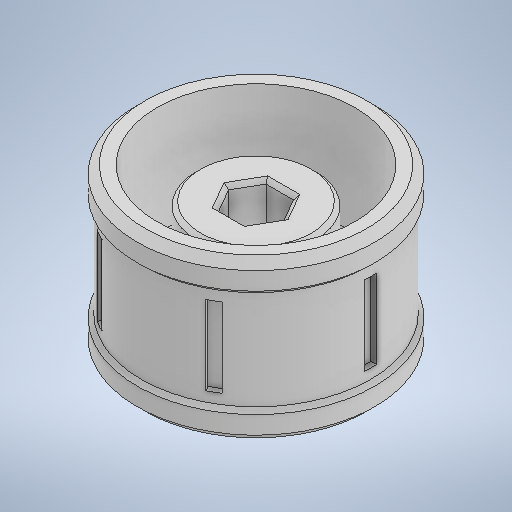
# Autodesk Inventor part: WHEEL RIM
Saved by Autodesk Inventor 2026.3 (Build 303398000, 398)
## iProperties
Created: 2026-10-19
Part Number: WHEEL RIM
Material: Generic
Document SubType Name: Modeling
Designer: Salim
Density: 1 g/cm^3
Appearance: Default
Author: Salim
Autodesk Inventor part; units mm, degrees
ref_plane "YZ Plane" through (0, 0, 0) normal (1, 0, 0) x (0, 1, 0)
ref_plane "XZ Plane" through (0, 0, 0) normal (0, 1, 0) x (-1, 0, 0)
sketch "Sketch1" plane through (0, 0, 0) normal (0, 1, 0) x (-1, 0, 0)
  line L0 (-3.4641, -6) -> (-6.9282, 0)
  line L1 (-6.9282, 0) -> (-3.4641, 6)
  line L2 (-3.4641, 6) -> (3.4641, 6)
  line L3 (3.4641, 6) -> (6.9282, 0)
  line L4 (6.9282, 0) -> (3.4641, -6)
  line L5 (3.4641, -6) -> (-3.4641, -6)
  circle A0 centre (0, 0) radius 40
  circle A1 centre (0, 0) radius 30
  circle A2 centre (0, 0) radius 15
  circle A3 centre (0, 0) radius 25
  dimension "hex" = 12
  dimension "tire" = 80
  dimension "rim" = 60
  dimension "d5" = 30
  dimension "d8" = 50
  constraints: 12 end point, 5 coincident, 4 centre point, 13 other
  measures "hex" distance between parallel lines of L5 L2
  measures "tire" diameter of A0
  measures "rim" diameter of A1
  measures "d5" diameter of A2
  measures "d8" diameter of A3
extrude "Extrusion1" add sketch "Sketch1" along normal blind 40 contours A1
ref_plane "Work Plane1" through (0, 20, 0) normal (0, -1, 0) x (1, 0, 0)
extrude "Extrusion3" add sketch "Sketch1" along normal blind 12 from surface at 20 contours A2
sketch "Sketch2" plane through (0, 20, 0) normal (0, -1, 0) x (1, 0, 0)
  circle A0 centre (0, 0) radius 30 projected
  circle A1 centre (0, 0) radius 15
  dimension "d12" = 30
  constraints: 1 centre point, 1 coincident
  measures "d12" diameter of A1
loft "Loft1" add profiles "Sketch1", "Sketch2" separate body contours L0 L1 L2 L3 L4 L5 | A1 | A2 | A3 / A1
shell "Shell1" thickness 5 removed faces 2 at (-27.8006, 0, -4.3875) at (8.8546, 0, 0.1391) bodies 2
combine bodies "Combine1" operation type add bodies to combine 2 1
fillet "Fillet1" radius 2 1 edges at (25, 6.6667, 0)
sketch "Sketch3" plane through (0, 15, 0) normal (0, -1, 0) x (1, 0, 0)
  circle A0 centre (0, 0) radius 2.25
  dimension "d19" = 4.5
  constraints: 1 centre point, 1 coincident
  measures "d19" diameter of A0
extrude "Extrusion4" cut sketch "Sketch3" against normal blind 12 bodies 2
sketch "Sketch4" plane through (0, 0, 0) normal (0, 0, 1) x (1, 0, 0)
  line L0 (30, 40) -> (-30, 40) projected
  line L1 (30, 0) -> (-30, 0) projected
  line L2 (29, 32.5) -> (31, 32.5)
  line L3 (31, 32.5) -> (31, 7.5)
  line L4 (31, 7.5) -> (29, 7.5)
  line L5 (29, 7.5) -> (29, 32.5)
  line L6 (30, 0) -> (30, 40) projected
  line L7 (29, 32.5) -> (31, 7.5) construction
  line L8 (31, 32.5) -> (29, 7.5) construction
  line L9 (0, -8) -> (0, 48) projected
  point P0 (0, 0)
  point P1 (30, 20)
  point P2 (30, 7.5)
  point P3 (30, 32.5)
  point P4 (0, 40)
  dimension "d22" = 40
  dimension "d23" = 2
  dimension "d24" = 25
  constraints: 12 end point, 3 midpoint, 2 parallel, 1 horizontal, 1 perpendicular
  measures "d22" distance between parallel lines of L0 L1
  measures "d23" distance of L3.end L4.end
  measures "d24" distance of L2.end L3.end
revolve "Revolution1" cut sketch "Sketch4" angle 360 about axis through (0, -10, 0) along (0, 1, 0) bodies 2 contours L6 L4 L5 L2
chamfer "Chamfer1" distance 2 angle 45 2 edges at (30, 40, 0) (30, 0, 0)
chamfer "Chamfer2" distance 1 angle 45 2 edges at (30, 7.5, 0) (30, 32.5, 0)
sketch "Sketch5" plane through (0, 20, 0) normal (0, -1, 0) x (1, 0, 0)
  line L0 (27.554, 1.5) -> (32.554, 1.5)
  line L1 (32.554, 1.5) -> (32.554, -1.5)
  line L2 (32.554, -1.5) -> (27.554, -1.5)
  line L3 (27.554, -1.5) -> (27.554, 1.5)
  line L4 (27.554, 1.5) -> (32.554, -1.5) construction
  line L5 (32.554, 1.5) -> (27.554, -1.5) construction
  point P0 (0, 0)
  point P1 (30.054, 0)
  dimension "d32" = 5
  dimension "d33" = 3
  constraints: 12 end point, 2 midpoint, 2 parallel, 1 horizontal, 1 perpendicular
  measures "d32" distance of L1.end L2.end
  measures "d33" distance of L0.end L1.end
extrude "Extrusion5" cut sketch "Sketch5" along normal mid plane 20 bodies 2
pattern_circular "Circular Pattern1" count 6 over 360 about axis through (0, -10, 0) along (0, 1, 0) of "Extrusion5" bodies 2
chamfer "Chamfer3" distance 1 angle 45 7 edges at (-5.1962, 32, -3) (-5.1962, 32, 3) (0, 32, 6) (5.1962, 32, 3) (5.1962, 32, -3) (0, 32, -6) (15, 32, 0)
equation "\"rim_width\" = 0.5 * tire"
equation "\"d12\" = d5"
body "Solid2"
